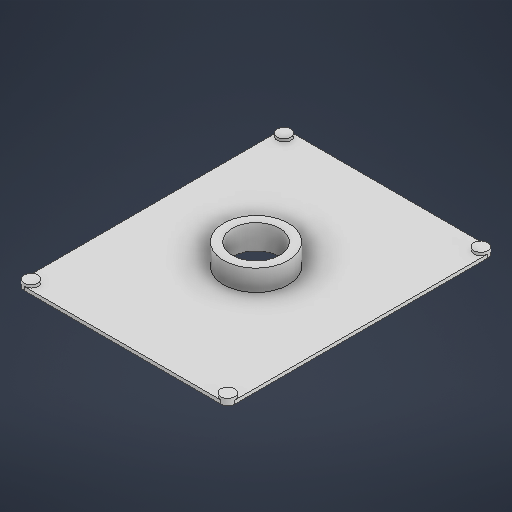
# Autodesk Inventor part: Tapa fianl
Saved by Autodesk Inventor 2027.1 (Build 311270010, 270A)
## iProperties
Created: 2026-09-19
Part Number: Tapa fianl
Material: Genérico
Document SubType Name: Modeling
Designer: irene
Density: 1 g/cm^3
Appearance: Valor por defecto
Author: irene
Autodesk Inventor part; units mm, degrees
ref_plane "YZ Plane" through (0, 0, 0) normal (1, 0, 0) x (0, 1, 0)
ref_plane "XZ Plane" through (0, 0, 0) normal (0, 1, 0) x (-1, 0, 0)
ref_plane "XY Plane" through (0, 0, 0) normal (0, 0, 1) x (1, 0, 0)
sketch "Boceto1" plane through (0, 0, 0) normal (0, 1, 0) x (-1, 0, 0)
  line L0 (-70, -90) -> (70, -90)
  line L1 (70, -90) -> (70, 90)
  line L2 (70, 90) -> (-70, 90)
  line L3 (-70, 90) -> (-70, -90)
  line L4 (-70, -90) -> (70, 90) construction
  line L5 (70, -90) -> (-70, 90) construction
  line L6 (-75, 95) -> (75, 95)
  line L7 (75, 95) -> (75, -95)
  line L8 (75, -95) -> (-75, -95)
  line L9 (-75, -95) -> (-75, 95)
  circle A0 centre (70, -90) radius 5
  circle A1 centre (-70, -90) radius 5
  circle A2 centre (-70, 90) radius 5
  circle A3 centre (70, 90) radius 5
  point P0 (0, 0)
  point P1 (70, 95)
  point P2 (-70, 95)
  point P3 (-75, 90)
  point P4 (-75, -90)
  point P5 (-70, -95)
  point P6 (70, -95)
  point P7 (75, -90)
  point P8 (75, 90)
  dimension "d0" = 180
  dimension "d1" = 140
  dimension "d2" = 5
  constraints: 20 end point, 4 centre point, 4 coincident, 4 parallel, 4 tangent, 2 midpoint, 2 perpendicular, 1 horizontal, 3 other
  measures "d0" distance of L0.end L1.end
  measures "d1" distance of L1.end L2.end
  measures "d2" distance between parallel lines of L2 L6
extrude "Extrusión2" add sketch "Boceto1" along normal blind 4.5 contours L3 A1 L0 | L0 A1 L3 | A0 L1 L0 | L0 L1 A0 | A2 L2 L3 | L3 L2 A2 | A3 L2 L1 | L1 L2 A3
extrude "Extrusión3" add sketch "Boceto1" along normal blind 2.5 contours A1 L3 A2 L2 A3 L1 A0 L0 | L0 A0 L8 A1 | A1 L9 A2 L3 | L1 A3 L7 A0 | A2 L6 A3 L2
sketch "Boceto2" plane through (0, 2.5, 0) normal (0, 1, 0) x (1, 0, 0)
  circle A0 centre (0, 0) radius 16.775
  dimension "d9" = 33.55
  constraints: 1 centre point, 1 coincident
  measures "d9" diameter of A0
extrude "Extrusión4" cut sketch "Boceto2" against normal blind 10
sketch "Boceto3" plane through (0, 2.5, 0) normal (0, 1, 0) x (1, 0, 0)
  circle A0 centre (0, 0) radius 23
  circle A1 centre (0, 0) radius 16.775 projected
  dimension "d12" = 46
  constraints: 1 centre point, 1 coincident
  measures "d12" diameter of A0
extrude "Extrusión5" add sketch "Boceto3" along normal blind 15
sketch "Boceto4" plane through (0, 0, 0) normal (1, 0, 0) x (0, 1, 0)
  point P0 (0, 0)
